fan-end-panel (Autodesk Fusion 360 design; units mm, degrees)
part number: 2026-11-27-18-27-05-652
Autodesk Fusion 360 part; units mm, degrees
sketch "Sketch1" plane through (0, 0, 0) normal (0, 1, 0) x (1, 0, 0)
  line L0 (-25, 25) -> (-25, -30)
  line L1 (-25, -30) -> (21.9089, -30)
  line L2 (21.9089, -30) -> (21.9089, 25)
  line L3 (21.9089, 25) -> (-25, 25)
  constraint vertical L0
  constraint perpendicular L0 L1
  constraint perpendicular L1 L2
  constraint perpendicular L0 L3
sketch "Sketch2" plane through (0, 0, 0) normal (0, 1, 0) x (1, 0, 0)
sketch "Sketch3" plane through (0, 0, 0) normal (0, 0, 1) x (1, 0, 0)
sketch "Sketch4" plane through (0, 0, 0) normal (0, 1, 0) x (1, 0, 0)
sketch "Sketch5" plane through (0, 0, 0) normal (0, 0, 1) x (1, 0, 0)
  line L0 (-70, -70) -> (70, -70)
  line L1 (70, -70) -> (70, 70)
  line L2 (70, 70) -> (-70, 70)
  line L3 (-70, 70) -> (-70, -70)
  line L4 (-70, -70) -> (70, 70) construction
  line L5 (70, -70) -> (-70, 70) construction
  dimension "d7" = 140
  dimension "d8" = 140
  constraint horizontal L0
  constraint perpendicular L0 L1
  constraint parallel L0 L2
  constraint parallel L1 L3
  constraint coincident L4 origin
  constraint coincident L5 origin
  measures "d7" distance of L1.end L2.end
  measures "d8" distance of L0.end L1.end
extrude "Extrude2" add sketch "Sketch5" along normal blind 3
sketch "Sketch6" plane through (0, 0, 0) normal (0, 0, -1) x (-1, 0, 0)
  line L0 (70, -70) -> (70, 70)
  line L1 (70, 70) -> (-70, 70)
  line L2 (-70, 70) -> (-70, -70)
  line L3 (-70, -70) -> (70, -70)
sketch "Sketch7" plane through (0, 0, 0) normal (0, 1, 0) x (1, 0, 0)
  line L0 (52.5, 52.5) -> (-52.5, 52.5) construction
  line L1 (-52.5, 52.5) -> (-52.5, -52.5) construction
  line L2 (-52.5, -52.5) -> (52.5, -52.5) construction
  line L3 (52.5, -52.5) -> (52.5, 52.5) construction
  line L4 (52.5, 52.5) -> (-52.5, -52.5) construction
  line L5 (-52.5, 52.5) -> (52.5, -52.5) construction
  dimension "d11" = 105
  dimension "d12" = 105
  constraint horizontal L0
  constraint perpendicular L0 L1
  constraint parallel L0 L2
  constraint parallel L1 L3
  constraint coincident L4 origin
  constraint coincident L5 origin
  measures "d11" distance of L1.end L2.end
  measures "d12" distance of L0.end L1.end
sketch "Sketch8" plane through (0, 0, 3) normal (0, 0, 1) x (1, 0, 0)
  line L0 (-70, 70) -> (-70, -70)
  line L1 (-70, -70) -> (70, -70)
  line L2 (70, -70) -> (70, 70)
  line L3 (70, 70) -> (-70, 70)
  line L4 (52.5, -52.5) -> (-52.5, -52.5) construction
  line L5 (-52.5, -52.5) -> (-52.5, 52.5) construction
  line L6 (-52.5, 52.5) -> (52.5, 52.5) construction
  line L7 (52.5, 52.5) -> (52.5, -52.5) construction
  line L8 (52.5, -52.5) -> (-52.5, 52.5) construction
  line L9 (-52.5, -52.5) -> (52.5, 52.5) construction
  circle A0 centre (52.5, -52.5) radius 2.25
  circle A1 centre (52.5, 52.5) radius 2.25
  circle A2 centre (-52.5, 52.5) radius 2.25
  circle A3 centre (-52.5, -52.5) radius 2.25
  circle A4 centre (0, 0) radius 58
  dimension "d13" = 105
  dimension "d14" = 105
  dimension "d15" = 4.5
  dimension "d16" = 4.5
  dimension "d17" = 4.5
  dimension "d18" = 4.5
  dimension "d19" = 116
  constraint horizontal L4
  constraint perpendicular L4 L5
  constraint parallel L4 L6
  constraint parallel L5 L7
  constraint coincident L8 A4.centre
  constraint coincident L9 A4.centre
  constraint coincident A4.centre origin
  constraint coincident L4.start L7.end
  constraint coincident L6.end L7.start
  constraint coincident L5.end L6.start
  constraint coincident L4.end L5.start
  measures "d13" distance of L5.end L6.end
  measures "d14" distance of L4.end L5.end
  measures "d15" diameter of A0
  measures "d16" diameter of A1
  measures "d17" diameter of A2
  measures "d18" diameter of A3
  measures "d19" diameter of A4
extrude "Extrude3" cut sketch "Sketch8" against normal through all contours A0 | A1 | A2 | A3 | A4
